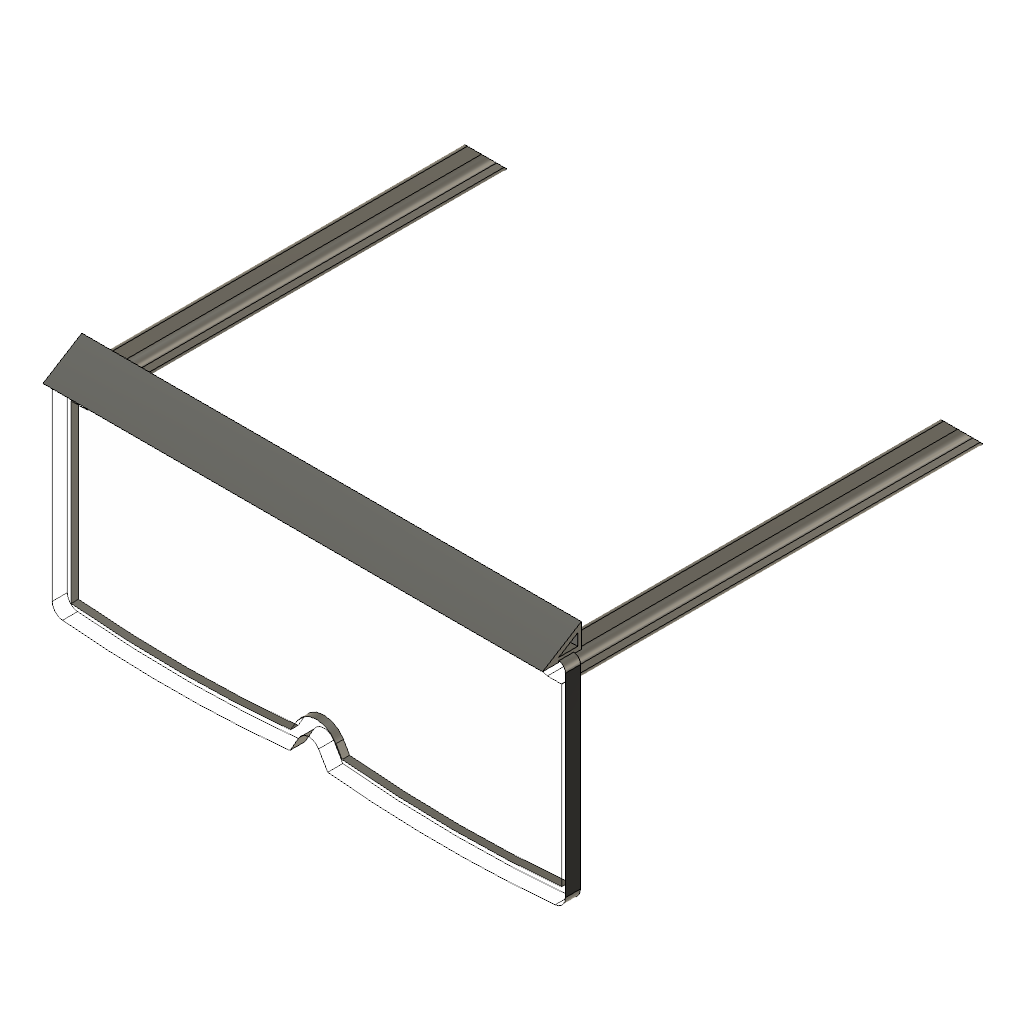
Clear Shield (Autodesk Fusion 360 design; units mm, degrees)
Autodesk Fusion 360 part; units mm, degrees
sketch "Sketch1" plane through (0, 0, 0) normal (0, 1, 0) x (1, 0, 0)
  line L0 (-80.01, -3.4569) -> (-80.01, -68.8753)
  arc A0 (-77.7733, -71.3971) -> (0, -71.12) centre (-40.005, 242.6494) ccw
  arc A1 (0, 0) -> (-76.5527, 0.3368) centre (-40.005, -392.7832) ccw
  line L1 (0, 0) -> (3.0504, -5.2835)
  line L2 (92.71, -3.4569) -> (92.71, -68.8753)
  arc A2 (12.7, -71.12) -> (90.4733, -71.3971) centre (52.705, 242.6494) ccw
  arc A3 (89.2527, 0.3368) -> (12.7, 0) centre (52.705, -392.7832) ccw
  line L3 (12.7, 0) -> (9.6496, -5.2835)
  arc A4 (12.7, -71.12) -> (0, -71.12) centre (6.35, -120.9247) ccw
  arc A5 (3.0504, -5.2835) -> (9.6496, -5.2835) centre (6.35, -3.3785) ccw
  arc A6 (-80.01, -68.8753) -> (-77.7733, -71.3971) centre (-77.47, -68.8753) ccw
  arc A7 (90.4733, -71.3971) -> (92.71, -68.8753) centre (90.17, -68.8753) ccw
  arc A8 (92.71, -3.4569) -> (89.2527, 0.3368) centre (88.9, -3.4569) ccw
  arc A9 (-76.5527, 0.3368) -> (-80.01, -3.4569) centre (-76.2, -3.4569) ccw
  point P0 (-80.01, 0)
  point P1 (-80.01, -71.12)
  point P2 (6.35, -10.9985)
  point P3 (12.7, 0)
  dimension "d1" = 80.01
  dimension "d2" = 71.12
  dimension "d14" = 12.7
  dimension "d17" = 3.81
  dimension "d18" = 2.54
  dimension "d19" = 2.54
  dimension "d20" = 3.81
  dimension "d21" = 3.81
  constraint coincident A1.start L1.start
  constraint tangent A2 A4
  constraint coincident A2.start A4.start
  constraint coincident A0.end A4.end
  constraint coincident P2 L1
  constraint tangent L1 A5
  constraint tangent L3 A5
  constraint tangent A0 A6
  constraint tangent L0 A6
  constraint tangent A2 A7
  constraint tangent L2 A7
  constraint tangent L2 A8
  constraint tangent A3 A8
  constraint tangent L0 A9
  constraint tangent A1 A9
  measures "d1" distance of A1.start P0
  measures "d2" distance of P0 P1
  measures "d14" distance of A1.start P2
  measures "d17" radius of A5
  measures "d18" radius of A6
  measures "d19" radius of A7
  measures "d20" radius of A8
  measures "d21" radius of A9
extrude "Extrude1" add sketch "Sketch1" along normal blind 2.54
sketch "Sketch2" plane through (0, 0, 0) normal (1, 0, 0) x (0, 1, 0)
  line L0 (2.54, 71.3971, 90.4733) -> (142.24, 71.3971, 90.4733)
  line L1 (142.24, 71.3971, 90.4733) -> (142.24, 63.7771, 90.4733)
  line L2 (142.24, 63.7771, 90.4733) -> (2.54, 63.7771, 90.4733)
  line L3 (2.54, 63.7771, 90.4733) -> (2.54, 71.3971, 90.4733)
  point P0 (2.54, 71.3971)
  dimension "d24" = 139.7
  dimension "d25" = 7.62
extrude "Extrude2" add sketch "Sketch2" along normal blind 2.159 contours L0 L1 L2 L3 in plane through (90.4733, 0, 0) normal (1, 0, 0)
move_face "OffsetFaces1" offset 2.54 1 faces at (90.4733, 49.1067, 68.8571)
move_face "MoveFace1" by (-1.27, 0, -1.27) 6 faces at (87.9333, 49.1067, 68.8571) (90.3463, 95.6733, 71.3971) (89.4996, 142.24, 68.8571) (92.1064, 2.54, 70.9847) (92.6323, 95.6733, 68.2243) (91.066, 95.6733, 63.7771)
chamfer "Chamfer1" distance 6.35 angle 45 1 edges at (89.0128, 142.24, 70.1271) tangent chain off
sketch "Sketch3" plane through (0, 2.54, 0) normal (0, 1, 0) x (-1, 0, 0)
  line L0 (-91.3623, 62.5071) -> (-91.3623, 70.1271)
  line L1 (-91.3623, 70.1271) -> (-86.6633, 70.1271)
  line L2 (-86.6633, 70.1271) -> (-86.6633, 62.5071)
  line L3 (-86.6633, 62.5071) -> (-91.3623, 62.5071)
  arc A0 (-90.4733, 71.3971) -> (-92.71, 68.8753) centre (-90.17, 68.8753) ccw
  line L4 (-92.71, 68.8753) -> (-92.71, 3.4569)
  arc A1 (-92.71, 3.4569) -> (-89.2527, -0.3368) centre (-88.9, 3.4569) ccw
  arc A2 (-89.2527, -0.3368) -> (-12.7, 0) centre (-52.705, 392.7832) ccw
  line L5 (-12.7, 0) -> (-9.6496, 5.2835)
  arc A3 (-3.0504, 5.2835) -> (-9.6496, 5.2835) centre (-6.35, 3.3785) ccw
  line L6 (-3.0504, 5.2835) -> (0, 0)
  arc A4 (0, 0) -> (76.5527, -0.3368) centre (40.005, 392.7832) ccw
  arc A5 (76.5527, -0.3368) -> (80.01, 3.4569) centre (76.2, 3.4569) ccw
  line L7 (80.01, 3.4569) -> (80.01, 68.8753)
  arc A6 (80.01, 68.8753) -> (77.7733, 71.3971) centre (77.47, 68.8753) ccw
  arc A7 (77.7733, 71.3971) -> (0, 71.12) centre (40.005, -242.6494) ccw
  arc A8 (-12.7, 71.12) -> (0, 71.12) centre (-6.35, 120.9247) ccw
  arc A9 (-12.7, 71.12) -> (-90.4733, 71.3971) centre (-52.705, -242.6494) ccw
  line L8 (78.6638, 62.5071) -> (73.9648, 62.5071)
  line L9 (73.9648, 62.5071) -> (73.9648, 70.1271)
  line L10 (73.9648, 70.1271) -> (78.6638, 70.1271)
  line L11 (78.6638, 70.1271) -> (78.6638, 62.5071)
  dimension "d31" = 4.699
  dimension "d32" = 7.62
  constraint horizontal L8
  constraint vertical L9
  constraint horizontal L10
  constraint vertical L11
  measures "d31" distance of L8.start L8.end
  measures "d32" distance of L8.start L10.end
extrude "Extrude3" add sketch "Sketch3" along normal blind 139.7 contours L8 L9 L10 L11
chamfer "Chamfer2" distance 6.35 angle 45 1 edges at (-76.3143, 142.24, 70.1271) tangent chain off
move_face "OffsetFaces2" offset 5.08 1 faces at (-73.9648, 93.5567, 65.0471)
move_face "OffsetFaces3" offset 5.08 1 faces at (86.6633, 93.5567, 65.0471)
fillet "Fillet1" radius 2.54 1 edges at (81.5833, 69.215, 70.1271)
fillet "Fillet2" radius 2.54 1 edges at (91.3623, 69.215, 70.1271)
fillet "Fillet3" radius 2.54 1 edges at (91.3623, 72.39, 62.5071)
fillet "Fillet4" radius 2.54 1 edges at (81.5833, 72.39, 62.5071)
fillet "Fillet5" radius 2.54 1 edges at (-68.8848, 69.215, 70.1271)
fillet "Fillet6" radius 2.54 1 edges at (-78.6638, 69.215, 70.1271)
fillet "Fillet7" radius 2.54 1 edges at (-78.6638, 72.39, 62.5071)
fillet "Fillet8" radius 2.54 1 edges at (-68.8848, 72.39, 62.5071)
sketch "Sketch4" plane through (0, 2.54, 0) normal (0, 1, 0) x (-1, 0, 0)
  line L0 (78.6638, 67.5871) -> (78.6638, 65.0471)
  arc A0 (76.1238, 62.5071) -> (78.6638, 65.0471) centre (76.1238, 65.0471) ccw
  line L1 (76.1238, 62.5071) -> (71.4248, 62.5071)
  arc A1 (68.8848, 65.0471) -> (71.4248, 62.5071) centre (71.4248, 65.0471) ccw
  line L2 (68.8848, 65.0471) -> (68.8848, 67.5871)
  arc A2 (71.4248, 70.1271) -> (68.8848, 67.5871) centre (71.4248, 67.5871) ccw
  line L3 (71.4248, 70.1271) -> (76.1238, 70.1271)
  arc A3 (78.6638, 67.5871) -> (76.1238, 70.1271) centre (76.1238, 67.5871) ccw
  line L4 (-88.8223, 70.1271) -> (-84.1233, 70.1271)
  arc A4 (-81.5833, 67.5871) -> (-84.1233, 70.1271) centre (-84.1233, 67.5871) ccw
  line L5 (-81.5833, 67.5871) -> (-81.5833, 65.0471)
  arc A5 (-84.1233, 62.5071) -> (-81.5833, 65.0471) centre (-84.1233, 65.0471) ccw
  line L6 (-84.1233, 62.5071) -> (-88.8223, 62.5071)
  arc A6 (-91.3623, 65.0471) -> (-88.8223, 62.5071) centre (-88.8223, 65.0471) ccw
  line L7 (-91.3623, 65.0471) -> (-91.3623, 67.5871)
  arc A7 (-88.8223, 70.1271) -> (-91.3623, 67.5871) centre (-88.8223, 67.5871) ccw
  arc A8 (-90.4733, 71.3971) -> (-92.71, 68.8753) centre (-90.17, 68.8753) ccw
  line L8 (-92.71, 68.8753) -> (-92.71, 3.4569)
  arc A9 (-92.71, 3.4569) -> (-89.2527, -0.3368) centre (-88.9, 3.4569) ccw
  arc A10 (-89.2527, -0.3368) -> (-12.7, 0) centre (-52.705, 392.7832) ccw
  line L9 (-12.7, 0) -> (-9.6496, 5.2835)
  arc A11 (-3.0504, 5.2835) -> (-9.6496, 5.2835) centre (-6.35, 3.3785) ccw
  line L10 (-3.0504, 5.2835) -> (0, 0)
  arc A12 (0, 0) -> (76.5527, -0.3368) centre (40.005, 392.7832) ccw
  arc A13 (76.5527, -0.3368) -> (80.01, 3.4569) centre (76.2, 3.4569) ccw
  line L11 (80.01, 3.4569) -> (80.01, 68.8753)
  arc A14 (80.01, 68.8753) -> (77.7733, 71.3971) centre (77.47, 68.8753) ccw
  arc A15 (77.7733, 71.3971) -> (0, 71.12) centre (40.005, -242.6494) ccw
  arc A16 (-12.7, 71.12) -> (0, 71.12) centre (-6.35, 120.9247) ccw
  arc A17 (-12.7, 71.12) -> (-90.4733, 71.3971) centre (-52.705, -242.6494) ccw
  line L12 (-88.9, 67.7468) -> (-88.9, 3.4569)
  arc A18 (-88.9, 3.4569) -> (-15.0221, 3.5981) centre (-52.705, 392.7832) ccw
  line L13 (-15.0221, 3.5981) -> (-12.9491, 7.1885)
  arc A19 (0.2491, 7.1885) -> (-12.9491, 7.1885) centre (-6.35, 3.3785) ccw
  line L14 (0.2491, 7.1885) -> (2.3221, 3.5981)
  arc A20 (2.3221, 3.5981) -> (76.2, 3.4569) centre (40.005, 392.7832) ccw
  line L15 (76.2, 3.4569) -> (76.2, 67.7468)
  arc A21 (76.2, 67.7468) -> (0.4819, 67.3406) centre (40.005, -242.6494) ccw
  arc A22 (-13.1819, 67.3406) -> (0.4819, 67.3406) centre (-6.35, 120.9247) ccw
  arc A23 (-13.1819, 67.3406) -> (-88.9, 67.7468) centre (-52.705, -242.6494) ccw
  dimension "d54" = -3.81
extrude "Extrude4" add sketch "Sketch4" along normal blind 2.54
sketch "Sketch5" plane through (0, 5.08, 0) normal (0, 1, 0) x (-1, 0, 0)
  arc A0 (71.4248, 70.1271) -> (69.0534, 68.497) centre (71.4248, 67.5871) ccw
  line L0 (71.4248, 70.1271) -> (76.1238, 70.1271)
  arc A1 (78.6638, 67.5871) -> (76.1238, 70.1271) centre (76.1238, 67.5871) ccw
  line L1 (78.6638, 67.5871) -> (78.6638, 65.0471)
  arc A2 (76.2, 62.5082) -> (78.6638, 65.0471) centre (76.1238, 65.0471) ccw
  line L2 (76.2, 62.5082) -> (76.2, 3.4569)
  arc A3 (2.3221, 3.5981) -> (76.2, 3.4569) centre (40.005, 392.7832) ccw
  line L3 (2.3221, 3.5981) -> (0.2491, 7.1885)
  arc A4 (0.2491, 7.1885) -> (-12.9491, 7.1885) centre (-6.35, 3.3785) ccw
  line L4 (-12.9491, 7.1885) -> (-15.0221, 3.5981)
  arc A5 (-88.9, 3.4569) -> (-15.0221, 3.5981) centre (-52.705, 392.7832) ccw
  line L5 (-88.9, 3.4569) -> (-88.9, 62.5083)
  arc A6 (-91.3623, 65.0471) -> (-88.9, 62.5083) centre (-88.8223, 65.0471) ccw
  line L6 (-91.3623, 65.0471) -> (-91.3623, 67.5871)
  arc A7 (-88.8223, 70.1271) -> (-91.3623, 67.5871) centre (-88.8223, 67.5871) ccw
  line L7 (-88.8223, 70.1271) -> (-84.1233, 70.1271)
  arc A8 (-81.7519, 68.4971) -> (-84.1233, 70.1271) centre (-84.1233, 67.5871) ccw
  arc A9 (-13.1819, 67.3406) -> (-81.7519, 68.4971) centre (-52.705, -242.6494) ccw
  arc A10 (-13.1819, 67.3406) -> (0.4819, 67.3406) centre (-6.35, 120.9247) ccw
  arc A11 (69.0534, 68.497) -> (0.4819, 67.3406) centre (40.005, -242.6494) ccw
  line L8 (-3.0504, 5.2835) -> (0, 0)
  arc A12 (0, 0) -> (76.5527, -0.3368) centre (40.005, 392.7832) ccw
  arc A13 (76.5527, -0.3368) -> (80.01, 3.4569) centre (76.2, 3.4569) ccw
  line L9 (80.01, 3.4569) -> (80.01, 68.8753)
  arc A14 (80.01, 68.8753) -> (77.7733, 71.3971) centre (77.47, 68.8753) ccw
  arc A15 (77.7733, 71.3971) -> (0, 71.12) centre (40.005, -242.6494) ccw
  arc A16 (-12.7, 71.12) -> (0, 71.12) centre (-6.35, 120.9247) ccw
  arc A17 (-12.7, 71.12) -> (-90.4733, 71.3971) centre (-52.705, -242.6494) ccw
  arc A18 (-90.4733, 71.3971) -> (-92.71, 68.8753) centre (-90.17, 68.8753) ccw
  line L10 (-92.71, 68.8753) -> (-92.71, 3.4569)
  arc A19 (-92.71, 3.4569) -> (-89.2527, -0.3368) centre (-88.9, 3.4569) ccw
  arc A20 (-89.2527, -0.3368) -> (-12.7, 0) centre (-52.705, 392.7832) ccw
  line L11 (-12.7, 0) -> (-9.6496, 5.2835)
  arc A21 (-3.0504, 5.2835) -> (-9.6496, 5.2835) centre (-6.35, 3.3785) ccw
  line L12 (-90.4733, 71.3971, 0) -> (-90.4733, 71.3971, -5.08)
  line L13 (-90.4733, 71.3971, 0) -> (-90.4733, 71.3971, 2.54)
  line L14 (-90.4733, 71.3971, 2.54) -> (-90.4733, 79.0171, 2.54)
  line L15 (-90.4733, 79.0171, 2.54) -> (-90.4733, 71.3971, -9.7426)
  line L16 (-90.4733, 71.3971, -9.7426) -> (-90.4733, 71.3971, -5.08)
  point P0 (-90.4733, 71.3971)
  dimension "d62" = 7.62
  constraint coincident P0 A17.end
extrude "Extrude6" add sketch "Sketch5" along normal blind 168.148 contours L12 L13 L14 L15 L16 in plane through (90.4733, 5.08, 0) normal (-1, 0, 0)
move_face "OffsetFaces4" offset 0.508 1 faces at (3.5206, -3.1084, 71.3971)
sketch "Sketch6" plane through (0, 0, 0) normal (0, 1, 0) x (1, 0, 0)
  line L0 (76.4733, -76.0171, 7.62) -> (66.4733, -76.0171, 7.62)
  line L1 (66.4733, -76.0171, 7.62) -> (66.4733, -74.0171, 7.62)
  line L2 (66.4733, -74.0171, 7.62) -> (76.4733, -74.0171, 7.62)
  line L3 (76.4733, -74.0171, 7.62) -> (76.4733, -76.0171, 7.62)
  point P0 (90.4733, -79.0171)
  dimension "d100" = 10
  dimension "d101" = 2
sketch "Sketch7" plane through (-77.6747, 0, 0) normal (-1, 0, 0) x (0, -1, 0)
  line L0 (0, 71.4089) -> (0, 70.8891)
  line L1 (0, 70.8891) -> (5.4814, 70.8891)
  line L2 (5.4814, 70.8891) -> (-7.62, 79.0171)
  line L3 (-7.62, 79.0171) -> (-7.62, 70.8891)
  line L4 (-7.62, 70.8891) -> (-5.08, 70.8891)
  line L5 (-5.08, 70.8891) -> (-5.08, 71.4089)
  line L6 (-5.08, 71.4089) -> (0, 71.4089)
  line L7 (-6.35, 72.39) -> (0, 72.39)
  line L8 (0, 72.39) -> (-6.35, 76.3295)
  line L9 (-6.35, 76.3295) -> (-6.35, 72.39)
  constraint horizontal L7
  constraint parallel L2 L8
  constraint perpendicular L7 L9
extrude "Extrude7" cut sketch "Sketch7" against normal blind 172.72 contours L7 L8 L9
extrude "Extrude8" cut sketch "Sketch6" against normal blind 3.81 contours L0 L1 L2 L3 in plane through (0, 7.62, 0) normal (0, 1, 0)
sketch "Sketch8" plane through (0, 7.62, 0) normal (0, 1, 0) x (-1, 0, 0)
  line L0 (-66.4733, 76.0171) -> (-66.4733, 74.0171)
  line L1 (-66.4733, 74.0171) -> (-76.4733, 74.0171)
  line L2 (-76.4733, 74.0171) -> (-76.4733, 76.0171)
  line L3 (-76.4733, 76.0171) -> (-66.4733, 76.0171)
  line L4 (-90.4733, 79.0171) -> (-90.4733, 70.8891)
  line L5 (-90.4733, 70.8891) -> (77.6747, 70.8891)
  line L6 (77.6747, 70.8891) -> (77.6747, 79.0171)
  line L7 (77.6747, 79.0171) -> (-90.4733, 79.0171)
  line L8 (-52.4733, 76.0171) -> (-42.4733, 76.0171)
  line L9 (-42.4733, 76.0171) -> (-42.4733, 74.0171)
  line L10 (-42.4733, 74.0171) -> (-52.4733, 74.0171)
  line L11 (-52.4733, 74.0171) -> (-52.4733, 76.0171)
  line L12 (-28.4733, 76.0171) -> (-18.4733, 76.0171)
  line L13 (-18.4733, 76.0171) -> (-18.4733, 74.0171)
  line L14 (-18.4733, 74.0171) -> (-28.4733, 74.0171)
  line L15 (-28.4733, 74.0171) -> (-28.4733, 76.0171)
  line L16 (-4.4733, 76.0171) -> (5.5267, 76.0171)
  line L17 (5.5267, 76.0171) -> (5.5267, 74.0171)
  line L18 (5.5267, 74.0171) -> (-4.4733, 74.0171)
  line L19 (-4.4733, 74.0171) -> (-4.4733, 76.0171)
  line L20 (19.5267, 76.0171) -> (29.5267, 76.0171)
  line L21 (29.5267, 76.0171) -> (29.5267, 74.0171)
  line L22 (29.5267, 74.0171) -> (19.5267, 74.0171)
  line L23 (19.5267, 74.0171) -> (19.5267, 76.0171)
  line L24 (43.5267, 76.0171) -> (53.5267, 76.0171)
  line L25 (53.5267, 76.0171) -> (53.5267, 74.0171)
  line L26 (53.5267, 74.0171) -> (43.5267, 74.0171)
  line L27 (43.5267, 74.0171) -> (43.5267, 76.0171)
  constraint horizontal L8
  constraint vertical L9
  constraint horizontal L10
  constraint vertical L11
  constraint horizontal L12
  constraint vertical L13
  constraint horizontal L14
  constraint vertical L15
  constraint horizontal L16
  constraint vertical L17
  constraint horizontal L18
  constraint vertical L19
  constraint horizontal L20
  constraint vertical L21
  constraint horizontal L22
  constraint vertical L23
  constraint horizontal L24
  constraint vertical L25
  constraint horizontal L26
  constraint vertical L27
extrude "Extrude9" cut sketch "Sketch8" against normal blind 3.81 contours L8 L9 L10 L11
extrude "Extrude10" cut sketch "Sketch8" against normal blind 3.81 contours L12 L13 L14 L15
extrude "Extrude11" cut sketch "Sketch8" against normal blind 3.81 contours L16 L17 L18 L19
extrude "Extrude12" cut sketch "Sketch8" against normal blind 3.81 contours L20 L21 L22 L23
extrude "Extrude13" cut sketch "Sketch8" against normal blind 3.81 contours L24 L25 L26 L27
sketch "Sketch12" plane through (0, 0, 0) normal (0, 1, 0) x (1, 0, 0)
sketch "Sketch13" plane through (0, 0, 70.8891) normal (0, 0, -1) x (1, 0, 0)
  line L0 (2.1946, -5.08) -> (-77.6747, -5.08)
  line L1 (-77.6747, -5.08) -> (-77.6747, -7.62)
  line L2 (-77.6747, -7.62) -> (90.4733, -7.62)
  line L3 (90.4733, -7.62) -> (90.4733, -5.08)
  line L4 (90.4733, -5.08) -> (10.5054, -5.08)
  line L5 (10.5054, -5.08) -> (10.5054, 0)
  line L6 (10.5054, 0) -> (90.4733, 0)
  line L7 (90.4733, 0) -> (90.4733, 5.4814)
  line L8 (90.4733, 5.4814) -> (-77.6747, 5.4814)
  line L9 (-77.6747, 5.4814) -> (-77.6747, 0)
  line L10 (-77.6747, 0) -> (2.1946, 0)
  line L11 (2.1946, 0) -> (2.1946, -5.08)
  line L12 (-53.7298, -6.8291) -> (-43.7298, -6.8291)
  line L13 (-43.7298, -6.8291) -> (-43.7298, -5.8291)
  line L14 (-43.7298, -5.8291) -> (-53.7298, -5.8291)
  line L15 (-53.7298, -5.8291) -> (-53.7298, -6.8291)
  line L16 (43.942, -6.858) -> (51.942, -6.858)
  line L17 (51.942, -6.858) -> (51.942, -5.858)
  line L18 (51.942, -5.858) -> (43.942, -5.858)
  line L19 (43.942, -5.858) -> (43.942, -6.858)
  dimension "d155" = 10
  dimension "d156" = 1
  dimension "d163" = 8
  dimension "d164" = 1
  constraint horizontal L12
  constraint vertical L13
  constraint horizontal L14
  constraint vertical L15
  constraint horizontal L16
  constraint vertical L17
  constraint horizontal L18
  constraint vertical L19
  measures "d155" distance of L12.start L12.end
  measures "d156" distance of L12.start L14.end
  measures "d163" distance of L16.start L16.end
  measures "d164" distance of L16.start L18.end
extrude "Extrude14" cut sketch "Sketch13" against normal blind 3.81 contours L12 L13 L14 L15
sketch "Sketch14" plane through (0, 7.62, 0) normal (0, 1, 0) x (-1, 0, 0)
  line L0 (53.5267, 76.0171) -> (53.5267, 74.0171)
  line L1 (53.5267, 74.0171) -> (43.5267, 74.0171)
  line L2 (43.5267, 74.0171) -> (43.5267, 76.0171)
  line L3 (43.5267, 76.0171) -> (53.5267, 76.0171)
  line L4 (29.5267, 76.0171) -> (29.5267, 74.0171)
  line L5 (29.5267, 74.0171) -> (19.5267, 74.0171)
  line L6 (19.5267, 74.0171) -> (19.5267, 76.0171)
  line L7 (19.5267, 76.0171) -> (29.5267, 76.0171)
  line L8 (5.5267, 76.0171) -> (5.5267, 74.0171)
  line L9 (5.5267, 74.0171) -> (-4.4733, 74.0171)
  line L10 (-4.4733, 74.0171) -> (-4.4733, 76.0171)
  line L11 (-4.4733, 76.0171) -> (5.5267, 76.0171)
  line L12 (-18.4733, 76.0171) -> (-18.4733, 74.0171)
  line L13 (-18.4733, 74.0171) -> (-28.4733, 74.0171)
  line L14 (-28.4733, 74.0171) -> (-28.4733, 76.0171)
  line L15 (-28.4733, 76.0171) -> (-18.4733, 76.0171)
  line L16 (-42.4733, 76.0171) -> (-42.4733, 74.0171)
  line L17 (-42.4733, 74.0171) -> (-52.4733, 74.0171)
  line L18 (-52.4733, 74.0171) -> (-52.4733, 76.0171)
  line L19 (-52.4733, 76.0171) -> (-42.4733, 76.0171)
  line L20 (-66.4733, 76.0171) -> (-66.4733, 74.0171)
  line L21 (-66.4733, 74.0171) -> (-76.4733, 74.0171)
  line L22 (-76.4733, 74.0171) -> (-76.4733, 76.0171)
  line L23 (-76.4733, 76.0171) -> (-66.4733, 76.0171)
  line L24 (-90.4733, 79.0171) -> (-90.4733, 70.8891)
  line L25 (-90.4733, 70.8891) -> (77.6747, 70.8891)
  line L26 (77.6747, 70.8891) -> (77.6747, 79.0171)
  line L27 (77.6747, 79.0171) -> (-90.4733, 79.0171)
  line L28 (4.3675, 70.8891, -0.7442) -> (-3.6325, 70.8891, -0.7442)
  line L29 (-3.6325, 70.8891, -0.7442) -> (-3.6325, 70.8891, -1.7442)
  line L30 (-3.6325, 70.8891, -1.7442) -> (4.3675, 70.8891, -1.7442)
  line L31 (4.3675, 70.8891, -1.7442) -> (4.3675, 70.8891, -0.7442)
  dimension "d159" = 8
  dimension "d160" = 1
extrude "Extrude15" cut sketch "Sketch14" along normal blind 3.81 contours L28 L29 L30 L31 in plane through (0, 7.62, 70.8891) normal (0, 0, 1)
sketch "Sketch15" plane through (0, 7.62, 0) normal (0, 1, 0) x (-1, 0, 0)
  line L0 (53.5267, 76.0171) -> (53.5267, 74.0171)
  line L1 (53.5267, 74.0171) -> (43.5267, 74.0171)
  line L2 (43.5267, 74.0171) -> (43.5267, 76.0171)
  line L3 (43.5267, 76.0171) -> (53.5267, 76.0171)
  line L4 (29.5267, 76.0171) -> (29.5267, 74.0171)
  line L5 (29.5267, 74.0171) -> (19.5267, 74.0171)
  line L6 (19.5267, 74.0171) -> (19.5267, 76.0171)
  line L7 (19.5267, 76.0171) -> (29.5267, 76.0171)
  line L8 (5.5267, 76.0171) -> (5.5267, 74.0171)
  line L9 (5.5267, 74.0171) -> (-4.4733, 74.0171)
  line L10 (-4.4733, 74.0171) -> (-4.4733, 76.0171)
  line L11 (-4.4733, 76.0171) -> (5.5267, 76.0171)
  line L12 (-18.4733, 76.0171) -> (-18.4733, 74.0171)
  line L13 (-18.4733, 74.0171) -> (-28.4733, 74.0171)
  line L14 (-28.4733, 74.0171) -> (-28.4733, 76.0171)
  line L15 (-28.4733, 76.0171) -> (-18.4733, 76.0171)
  line L16 (-42.4733, 76.0171) -> (-42.4733, 74.0171)
  line L17 (-42.4733, 74.0171) -> (-52.4733, 74.0171)
  line L18 (-52.4733, 74.0171) -> (-52.4733, 76.0171)
  line L19 (-52.4733, 76.0171) -> (-42.4733, 76.0171)
  line L20 (-66.4733, 76.0171) -> (-66.4733, 74.0171)
  line L21 (-66.4733, 74.0171) -> (-76.4733, 74.0171)
  line L22 (-76.4733, 74.0171) -> (-76.4733, 76.0171)
  line L23 (-76.4733, 76.0171) -> (-66.4733, 76.0171)
  line L24 (-90.4733, 79.0171) -> (-90.4733, 70.8891)
  line L25 (-90.4733, 70.8891) -> (77.6747, 70.8891)
  line L26 (77.6747, 70.8891) -> (77.6747, 79.0171)
  line L27 (77.6747, 79.0171) -> (-90.4733, 79.0171)
extrude "Extrude16" cut sketch "Sketch13" against normal blind 3.81 contours L16 L17 L18 L19
